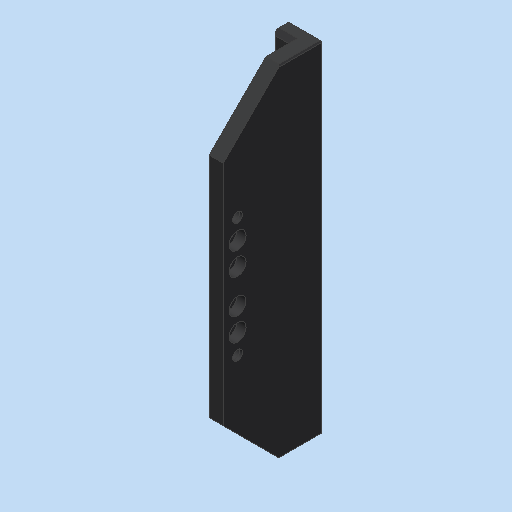
# Autodesk Inventor part: MM0861AN100_G01_121
Saved by Autodesk Inventor 2023.3 (Build 273359000, 359)
## iProperties
Created: 2018-10-19
Part Number: MM0861AN100_G01_121
Material: 1.2379 X155CrVMo 12-1
Document SubType Name: Modeling
Designer: Rose
Density: 7.85 g/cm^3
Appearance: Blau
Mass: 177.29 g
Surface Area: 109.771 cm^2
Volume: 22.5848 cm^3
MaxAbmaße: 0 x 0 x 0 (FM)
AnP_Material_aktuell: =<Material>
AnP_Kommentar_aktuell: =<Comments>
Author: Rose
Keywords: Präzi.Fl.40x12x123
Comments: HRC 56±2
Revision Number: 01
Autodesk Inventor part; units mm, degrees
ref_plane "YZ Plane" through (0, 0, 0) normal (1, 0, 0) x (0, 1, 0)
ref_plane "XZ Plane" through (0, 0, 0) normal (0, 1, 0) x (-1, 0, 0)
ref_plane "XY Plane" through (0, 0, 0) normal (0, 0, 1) x (1, 0, 0)
sketch "Skizze1" plane through (0, 0, 0) normal (0, 0, 1) x (1, 0, 0)
  line L0 (0, 37) -> (0, -12) projected
  line L1 (-9.4, 0) -> (7.4, 0) projected
  line L2 (0, -5) -> (0, 25)
  line L3 (0, 25) -> (-7, 25)
  line L4 (-7, 25) -> (-7, 30)
  line L5 (-7, 30) -> (5, 30)
  line L6 (5, 30) -> (5, -5)
  line L7 (5, -5) -> (0, -5)
  dimension "d0" = 5
  dimension "d2" = 5
  dimension "d3" = 5
  dimension "d4" = 12
  dimension "d15" = 25
  constraints: 12 end point, 3 perpendicular, 2 parallel, 2 point on line
  measures "d0" distance between parallel lines of L7 L1
  measures "d2" distance between parallel lines of L3 L5
  measures "d3" distance between parallel lines of L6 L0
  measures "d4" distance between parallel lines of L4 L6
  measures "d15" distance between parallel lines of L1 L3
extrude "Extrusion1" add sketch "Skizze1" along normal mid plane 120
sketch "Skizze2" plane through (5, -5, 60) normal (1, 0, 0) x (0, 0, -1)
  line L0 (-24, 5) -> (144, 5) projected
  line L1 (60, -7) -> (60, 42) projected
  point P0 (46, 5)
  point P1 (74, 5)
  point P2 (54, 5)
  point P3 (66, 5)
  dimension "d7" = 28
  dimension "d33" = 12
  constraints: 3 point on line, 2 symmetric about line
  measures "d7" distance of point (74, 5) point (46, 5)
  measures "d33" distance of point (66, 5) point (54, 5)
hole "Bohrung1" at (5, 0, 14) at (5, 0, -14) at (5, 0, 6) at (5, 0, -6) direction (-1, 0, 0) diameter 3.4 end through all counterbore diameter 6 counterbore depth 3.2
sketch "Skizze3" plane through (0, -5, 60) normal (-1, 0, 0) x (0, 0, 1)
  line L0 (-60, 42) -> (-60, -7) projected
  line L1 (-144, 5) -> (24, 5) projected
  point P0 (-81, 5)
  point P1 (-39, 5)
  dimension "d25" = 42
  constraints: 1 point on line, 1 symmetric about line
  measures "d25" distance of point (-39, 5) point (-81, 5)
hole "Bohrung2" at (0, 0, -21) at (0, 0, 21) direction (1, 0, 0) diameter 3.5 end through all counterbore diameter 4 counterbore depth 4
chamfer "Fase1" distance 2 angle 30 2 edges at (-3.5, 25, 60) (-3.5, 25, -60) measured on face at (-4.6667, 25, -20)
chamfer "Fase2" distance 0.5 angle 45 9 edges at (-7, 25, 0) (-7, 30, 0) (5, 30, 0) (-1, 30, -60) (-7, 28.0774, -60) (5, 12.5, -60) (-1, 30, 60) (-7, 28.0774, 60) (5, 12.5, 60)
chamfer "Fase3" distance 20 angle 45 2 edges at (2.25, -5, 60) (2.25, -5, -60)
